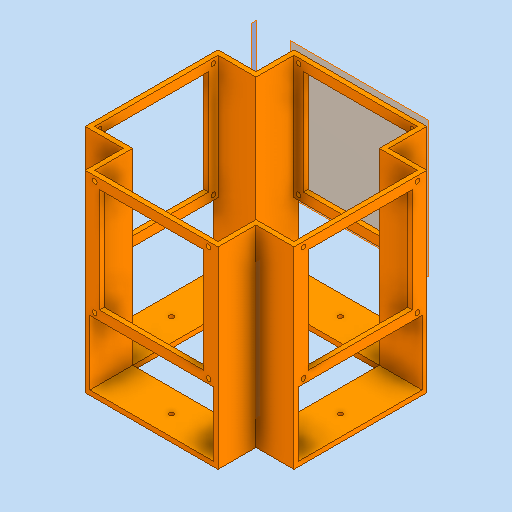
# Autodesk Inventor part: Armadura_Interna
Saved by Autodesk Inventor 2027 (Build 310192000, 192)
## iProperties
Created: 2026-11-03
Part Number: Armadura_Interna
Material: Plástico PMMA
Document SubType Name: Modeling
Designer: alex
Density: 1.188 g/cm^3
Appearance: Policarbonato - Claro
Author: alex
Autodesk Inventor part; units mm, degrees
ref_plane "YZ Plane" through (0, 0, 0) normal (1, 0, 0) x (0, 1, 0)
ref_plane "XZ Plane" through (0, 0, 0) normal (0, 1, 0) x (-1, 0, 0)
ref_plane "XY Plane" through (0, 0, 0) normal (0, 0, 1) x (1, 0, 0)
sketch "Boceto1" plane through (0, 0, 0) normal (0, 0, 1) x (1, 0, 0)
  circle A0 centre (-60, 60) radius 2.5
  circle A1 centre (-60, -60) radius 2.5
  circle A2 centre (60, 60) radius 2.5
  circle A3 centre (60, -60) radius 2.5
  line L0 (-65, 65) -> (65, 65)
  line L1 (65, 65) -> (65, -65)
  line L2 (65, -65) -> (-65, -65)
  line L3 (-65, -65) -> (-65, 65)
  line L4 (-55, 55) -> (55, 55)
  line L5 (55, 55) -> (55, -55)
  line L6 (55, -55) -> (-55, -55)
  line L7 (-55, -55) -> (-55, 55)
  point P0 (0, 0)
  dimension "d0" = 5
  dimension "d1" = 60
  dimension "d2" = 60
  dimension "d3" = 5
  dimension "d4" = 5
  dimension "d5" = 5
  dimension "d6" = 60
  dimension "d7" = 60
  dimension "d8" = 60
  dimension "d9" = 60
  dimension "d10" = 60
  dimension "d11" = 60
  dimension "d12" = 5
  dimension "d14" = 5
  dimension "d15" = 5
  dimension "d16" = 5
  dimension "d18" = 5
  dimension "d19" = 5
  dimension "d20" = 5
  dimension "d24" = 5
  constraints: 16 end point, 4 centre point, 4 parallel, 2 horizontal, 2 perpendicular
  measures "d0" diameter of A0
  measures "d1" horizontal distance of point (0, 0) A0.centre
  measures "d2" horizontal distance of point (0, 0) A0.centre
  measures "d3" diameter of A1
  measures "d4" diameter of A2
  measures "d5" diameter of A3
  measures "d6" horizontal distance of point (0, 0) A2.centre
  measures "d7" horizontal distance of point (0, 0) A2.centre
  measures "d8" horizontal distance of point (0, 0) A3.centre
  measures "d9" horizontal distance of point (0, 0) A3.centre
  measures "d10" horizontal distance of point (0, 0) A1.centre
  measures "d11" horizontal distance of point (0, 0) A1.centre
  measures "d12" distance from line of L7 A0.centre
  measures "d14" distance from line of L5 A2.centre
  measures "d15" distance from line of L1 A2.centre
  measures "d16" distance from line of A3.centre L6
  measures "d18" distance from line of A2.centre L0
  measures "d19" distance from line of L4 A2.centre
  measures "d20" distance from line of L2 A1.centre
  measures "d24" distance from line of L3 A0.centre
extrude "Extrusión1" add sketch "Boceto1" against normal blind 5
ref_plane "Plano de trabajo1" through (0, 0, -220) normal (0, 0, 1) x (1, 0, 0)
sketch "Boceto2" plane through (0, 0, -220) normal (0, 0, 1) x (1, 0, 0)
  line L0 (-65, 65) -> (65, 65)
  line L1 (65, 65) -> (65, -65)
  circle A0 centre (-60, 60) radius 2.5 projected
  circle A1 centre (-60, 60) radius 2.5
  circle A2 centre (-60, -60) radius 2.5 projected
  circle A3 centre (-60, -60) radius 2.5
  circle A4 centre (60, -60) radius 2.5 projected
  circle A5 centre (60, -60) radius 2.5
  circle A6 centre (60, 60) radius 2.5 projected
  circle A7 centre (60, 60) radius 2.5
  line L2 (-65, -65) -> (-65, 65) projected
  line L3 (-65, 65) -> (65, 65)
  line L4 (65, 65) -> (65, -65)
  line L5 (65, -65) -> (-65, -65)
  line L6 (-65, -65) -> (-65, 65)
  line L7 (-55, 55) -> (-55, -55) projected
  line L8 (-55, -55) -> (55, -55) projected
  line L9 (-55, 55) -> (55, 55)
  line L10 (55, 55) -> (55, -55)
  line L11 (55, -55) -> (-55, -55)
  line L12 (-55, -55) -> (-55, 55)
  point P0 (0, 0)
  constraints: 20 end point, 4 centre point, 4 coincident, 4 parallel, 3 horizontal, 3 perpendicular
extrude "Extrusión2" add sketch "Boceto2" along normal blind 5
ref_plane "Plano de trabajo2" through (110, -65, 0) normal (1, 0, 0) x (0, 0, -1)
ref_plane "Plano de trabajo3" through (-110, -65, -220) normal (-1, 0, 0) x (0, 0, 1)
sketch "Boceto3" plane through (-110, -65, -220) normal (-1, 0, 0) x (0, 0, 1)
  line L0 (0, 130) -> (0, 0) projected
  line L1 (220, 130) -> (215, 130) projected
  line L2 (0, 0) -> (220, 0)
  line L3 (220, 0) -> (220, 130)
  line L4 (220, 130) -> (0, 130)
  line L5 (0, 130) -> (0, 0)
  line L6 (45, 0) -> (175, 0)
  line L7 (175, 0) -> (175, 130)
  line L8 (175, 130) -> (45, 130)
  line L9 (45, 130) -> (45, 0)
  line L10 (55, 10) -> (165, 10)
  line L11 (165, 10) -> (165, 120)
  line L12 (165, 120) -> (55, 120)
  line L13 (55, 120) -> (55, 10)
  circle A0 centre (50, 5) radius 2.5
  circle A1 centre (170, 5) radius 2.5
  circle A2 centre (170, 125) radius 2.5
  circle A3 centre (50, 125) radius 2.5
  point P0 (220, 65)
  point P1 (45, 130)
  dimension "d29" = 45
  dimension "d30" = 45
  dimension "d31" = 120
  dimension "d32" = 5
  dimension "d33" = 5
  dimension "d34" = 5
  dimension "d35" = 5
  dimension "d36" = 5
  dimension "d37" = 5
  dimension "d38" = 5
  dimension "d39" = 5
  dimension "d40" = 5
  dimension "d41" = 5
  dimension "d42" = 5
  dimension "d43" = 5
  dimension "d44" = 5
  dimension "d45" = 5
  dimension "d46" = 5
  constraints: 24 end point, 6 parallel, 4 centre point, 4 coincident, 3 horizontal, 3 perpendicular, 2 point on line
  measures "d29" distance between parallel lines of L9 L0
  measures "d30" distance between parallel lines of L3 L7
  measures "d31" distance of point (170, 5) point (50, 5)
  measures "d32" distance from line of L7 point (170, 5)
  measures "d33" distance from line of point (170, 125) L8
  measures "d34" distance from line of L7 point (170, 125)
  measures "d35" distance from line of L6 point (170, 5)
  measures "d36" distance from line of L9 point (50, 5)
  measures "d37" distance from line of L8 point (50, 125)
  measures "d38" distance from line of L9 point (50, 125)
  measures "d39" diameter of A0
  measures "d40" diameter of A1
  measures "d41" diameter of A2
  measures "d42" diameter of A3
  measures "d43" distance from line of A0.centre L13
  measures "d44" distance from line of A0.centre L10
  measures "d45" distance from line of A2.centre L11
  measures "d46" distance from line of A2.centre L12
extrude "Extrusión3" add sketch "Boceto3" against normal blind 5 contours L4 L7 L2 L9
sketch "Boceto4" plane through (110, -65, 0) normal (1, 0, 0) x (0, 0, -1)
  line L0 (175, 0) -> (45, 0)
  line L1 (45, 0) -> (45, 130)
  line L2 (45, 130) -> (175, 130)
  line L3 (175, 130) -> (175, 0)
  circle A0 centre (50, 5) radius 2.5 projected
  circle A1 centre (50, 5) radius 2.5
  circle A2 centre (170, 5) radius 2.5 projected
  circle A3 centre (170, 5) radius 2.5
  circle A4 centre (170, 125) radius 2.5 projected
  circle A5 centre (170, 125) radius 2.5
  circle A6 centre (50, 125) radius 2.5 projected
  circle A7 centre (50, 125) radius 2.5
  line L4 (165, 10) -> (165, 120) projected
  line L5 (55, 120) -> (165, 120) projected
  line L6 (165, 10) -> (55, 10)
  line L7 (55, 10) -> (55, 120)
  line L8 (55, 120) -> (165, 120)
  line L9 (165, 120) -> (165, 10)
  point P0 (0, 65)
  constraints: 16 end point, 4 centre point, 4 coincident, 4 parallel, 2 horizontal, 2 perpendicular
extrude "Extrusión4" add sketch "Boceto4" against normal blind 5
sketch "Boceto5" plane through (-110, 65, -45) normal (0, 1, 0) x (1, 0, 0)
  line L0 (0, 130) -> (5, 130) projected
  line L1 (0, 130) -> (0, 135)
  line L2 (45, 175) -> (40, 175)
  line L3 (40, 175) -> (40, 135)
  line L4 (40, 135) -> (0, 135)
  line L5 (0, 130) -> (45, 130)
  line L6 (45, 130) -> (45, 175)
  line L7 (0, 0) -> (5, 0) projected
  line L8 (0, 0) -> (0, -5)
  line L9 (45, -45) -> (40, -45)
  line L10 (40, -45) -> (40, -5)
  line L11 (40, -5) -> (0, -5)
  line L12 (0, 0) -> (0, 130) projected
  line L13 (0, 0) -> (45, 0)
  line L14 (45, 0) -> (45, -45)
  line L15 (45, -45) -> (175, -45) projected
  line L16 (175, -45) -> (180, -45)
  line L17 (220, 0) -> (215, 0) projected
  line L18 (220, 0) -> (220, -5)
  line L19 (220, -5) -> (180, -5)
  line L20 (180, -5) -> (180, -45)
  line L21 (175, -45) -> (175, 0)
  line L22 (175, 0) -> (220, 0)
  line L23 (175, 175) -> (180, 175)
  line L24 (220, 130) -> (220, 135)
  line L25 (220, 135) -> (180, 135)
  line L26 (180, 135) -> (180, 175)
  line L27 (175, 175) -> (45, 175) projected
  line L28 (175, 175) -> (175, 130)
  line L29 (175, 130) -> (220, 130)
  point P0 (110, -45)
  dimension "d51" = 5
  dimension "d52" = 5
  dimension "d53" = 5
  dimension "d54" = 5
  dimension "d55" = 5
  dimension "d56" = 5
  dimension "d57" = 5
  dimension "d58" = 5
  constraints: 48 end point, 10 perpendicular, 6 point on line, 5 vertical, 4 horizontal, 2 parallel
  measures "d51" distance of L0.start L1.end
  measures "d52" distance of L2.start L2.end
  measures "d53" distance of L7.start L8.end
  measures "d54" distance of L9.start L9.end
  measures "d55" distance of L15.end L16.end
  measures "d56" distance of L17.start L18.end
  measures "d57" distance of L23.start L23.end
  measures "d58" distance of L24.start L24.end
extrude "Extrusión5" add sketch "Boceto5" against normal blind 130
sketch "Boceto6" plane through (-70, -65, 0) normal (0, -1, 0) x (1, 0, 0)
  line L0 (5, -5) -> (135, -5) projected
  line L1 (135, -5) -> (135, 0)
  line L2 (140, 0) -> (140, -40) projected
  line L3 (135, 0) -> (140, 0)
  line L4 (140, -40) -> (180, -40) projected
  line L5 (140, 0) -> (140, -40)
  line L6 (180, -40) -> (180, -180) projected
  line L7 (140, -40) -> (180, -40)
  line L8 (180, -40) -> (180, -45)
  line L9 (175, -45) -> (175, -175) projected
  line L10 (180, -45) -> (175, -45)
  line L11 (175, -45) -> (135, -45)
  line L12 (135, -45) -> (135, -5)
  line L13 (5, -45) -> (5, -5) projected
  line L14 (5, -45) -> (5, 0)
  line L15 (0, -40) -> (0, 0) projected
  line L16 (5, 0) -> (0, 0)
  line L17 (0, 0) -> (0, -40)
  line L18 (0, -40) -> (-40, -40) projected
  line L19 (0, -40) -> (-40, -40)
  line L20 (-40, -40) -> (-40, -45)
  line L21 (-40, -45) -> (5, -45)
  line L22 (5, -215) -> (5, -175) projected
  line L23 (5, -175) -> (-40, -175)
  line L24 (-40, -40) -> (-40, -180) projected
  line L25 (-40, -175) -> (-40, -180)
  line L26 (0, -180) -> (0, -220) projected
  line L27 (-40, -180) -> (0, -180)
  line L28 (0, -180) -> (0, -220)
  line L29 (0, -220) -> (5, -220)
  line L30 (5, -220) -> (5, -175)
  line L31 (135, -175) -> (135, -215) projected
  line L32 (135, -175) -> (180, -175)
  line L33 (135, -175) -> (135, -220)
  line L34 (135, -220) -> (140, -220)
  line L35 (140, -220) -> (140, -180)
  line L36 (140, -180) -> (180, -180) projected
  line L37 (140, -180) -> (180, -180)
  line L38 (180, -175) -> (180, -180)
  point P0 (70, 0)
  constraints: 52 end point, 16 perpendicular, 11 point on line, 4 collinear, 2 vertical, 1 horizontal
extrude "Extrusión6" add sketch "Boceto6" along normal blind 73 contours L1 L3 L2 L4 L6 L10 L11 L12 | L23 L22 L30 L29 L26 L27 L24 | L13 L21 L20 L18 L15 L16 L14 | L32 L6 L36 L35 L34 L33 L31
sketch "Boceto7" plane through (65, 65, -45) normal (-1, 0, 0) x (0, 0, 1)
  line L0 (45, -203) -> (0, -203) projected
  line L1 (0, 0) -> (0, -203) projected
  line L2 (45, -203) -> (0, -203)
  line L3 (0, -203) -> (0, -198)
  line L4 (0, -198) -> (45, -198)
  line L5 (45, -198) -> (45, -203)
  point P0 (45, -65)
  dimension "d63" = 5
  constraints: 8 end point, 2 parallel, 1 horizontal, 1 perpendicular, 1 point on line
  measures "d63" distance of L2.end L3.end
extrude "Extrusión7" add sketch "Boceto7" along normal blind 130
sketch "Boceto8" plane through (-65, 65, -45) normal (0, 0, -1) x (-1, 0, 0)
  line L0 (45, -203) -> (-175, -203) projected
  line L1 (-130, -198) -> (0, -198) projected
  line L2 (45, -203) -> (0, -203)
  line L3 (0, -203) -> (0, -198)
  line L4 (0, -198) -> (45, -198)
  line L5 (45, -198) -> (45, -203)
  point P0 (-65, -65)
  constraints: 8 end point, 2 parallel, 1 horizontal, 1 perpendicular
extrude "Extrusión8" add sketch "Boceto8" along normal blind 130
sketch "Boceto9" plane through (-65, 65, -175) normal (1, 0, 0) x (0, 0, -1)
  line L0 (45, -130) -> (45, -203) projected
  line L1 (45, -203) -> (0, -203)
  line L2 (0, -203) -> (0, -198)
  line L3 (0, -198) -> (45, -198)
  line L4 (45, -198) -> (45, -203)
  point P0 (-175, -65)
  point P1 (45, -198)
  constraints: 8 end point, 2 parallel, 1 horizontal, 1 perpendicular
extrude "Extrusión9" add sketch "Boceto9" along normal blind 130
sketch "Boceto10" plane through (65, 65, -175) normal (0, 0, 1) x (1, 0, 0)
  line L0 (-130, -198) -> (0, -198) projected
  line L1 (45, -203) -> (0, -203)
  line L2 (0, -203) -> (0, -198)
  line L3 (0, -198) -> (45, -198)
  line L4 (45, -198) -> (45, -203)
  point P0 (-65, -65)
  constraints: 8 end point, 2 parallel, 1 horizontal, 1 perpendicular
extrude "Extrusión10" add sketch "Boceto10" along normal blind 130
sketch "Boceto11" plane through (-110, -133, -45) normal (0, 1, 0) x (1, 0, 0)
  line L0 (45, 130) -> (175, 130) projected
  line L1 (45, 130) -> (175, 130)
  line L2 (175, 130) -> (175, 0)
  line L3 (175, 0) -> (45, 0)
  line L4 (45, 0) -> (45, 130)
  line L5 (45, 65) -> (175, 65)
  line L6 (110, 130) -> (110, 0)
  line L7 (110, 65) -> (21, 65)
  line L8 (110, 65) -> (199, 65)
  line L9 (110, 65) -> (110, 154)
  line L10 (110, 65) -> (110, -24)
  circle A0 centre (21, 65) radius 2.5
  circle A1 centre (110, 154) radius 2.5
  circle A2 centre (199, 65) radius 2.5
  circle A3 centre (110, -24) radius 2.5
  point P0 (110, -45)
  dimension "d72" = 89
  dimension "d73" = 89
  dimension "d74" = 89
  dimension "d75" = 89
  dimension "d76" = 5
  dimension "d77" = 5
  dimension "d78" = 5
  dimension "d79" = 5
  constraints: 20 end point, 5 midpoint, 4 centre point, 4 coincident, 4 point on line, 2 parallel, 1 horizontal, 1 perpendicular
  measures "d72" distance of L7.start L7.end
  measures "d73" distance of L7.start L8.end
  measures "d74" distance of L7.start L9.end
  measures "d75" distance of L7.start L10.end
  measures "d76" diameter of A0
  measures "d77" diameter of A1
  measures "d78" diameter of A2
  measures "d79" diameter of A3
hole "Agujero1" at (65, -133, -45) at (0, -133, -199) at (-89, -133, -110) at (89, -133, -110) at (0, -133, -21) direction (0, -1, 0) diameter 5 end through all
